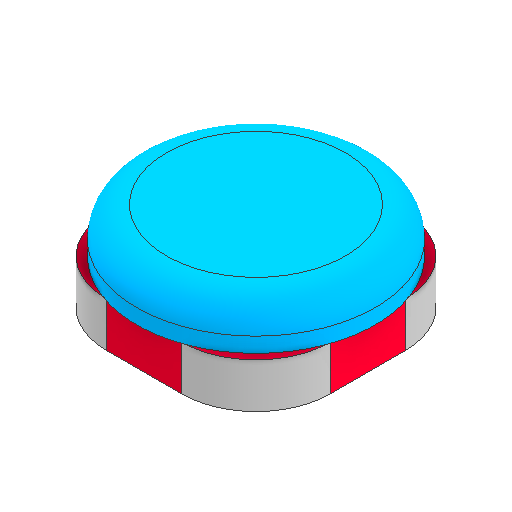
# Autodesk Inventor part: Button
Saved by Autodesk Inventor 2027.1 (Build 311270010, 270A)
## iProperties
Created: 2026-10-31
Part Number: Button
Material: Generic
Document SubType Name: Modeling
Designer: MSIPC
Density: 1 g/cm^3
Appearance: Default
Author: MSIPC
Autodesk Inventor part; units mm, degrees
ref_plane "YZ Plane" through (0, 0, 0) normal (1, 0, 0) x (0, 1, 0)
ref_plane "XZ Plane" through (0, 0, 0) normal (0, 1, 0) x (-1, 0, 0)
ref_plane "XY Plane" through (0, 0, 0) normal (0, 0, 1) x (1, 0, 0)
sketch "Sketch1" plane through (0, 0, 0) normal (0, 1, 0) x (-1, 0, 0)
  circle A0 centre (0, 0) radius 8
  dimension "d0" = 16
  constraints: 1 centre point, 1 coincident
  measures "d0" diameter of A0
extrude "Extrusion1" add sketch "Sketch1" along normal blind 3
fillet "Fillet1" radius 2 1 edges at (8, 3, 0)
sketch "Sketch2" plane through (0, 0, 0) normal (0, -1, 0) x (1, 0, 0)
  line L0 (7.5, 7.5) -> (7.5, -7.5)
  line L1 (7.5, -7.5) -> (-7.5, -7.5)
  line L2 (-7.5, -7.5) -> (-7.5, 7.5)
  line L3 (-7.5, 7.5) -> (7.5, 7.5)
  line L4 (7.5, 7.5) -> (-7.5, -7.5) construction
  line L5 (7.5, -7.5) -> (-7.5, 7.5) construction
  point P0 (0, 0)
  constraints: 12 end point, 2 midpoint, 2 parallel, 1 perpendicular, 1 vertical
extrude "Extrusion2" add sketch "Sketch2" along normal blind 3
fillet "Fillet2" radius 5 4 edges at (-7.5, -1.5, 7.5) (7.5, -1.5, 7.5) (7.5, -1.5, -7.5) (-7.5, -1.5, -7.5)
body "Solid1"
